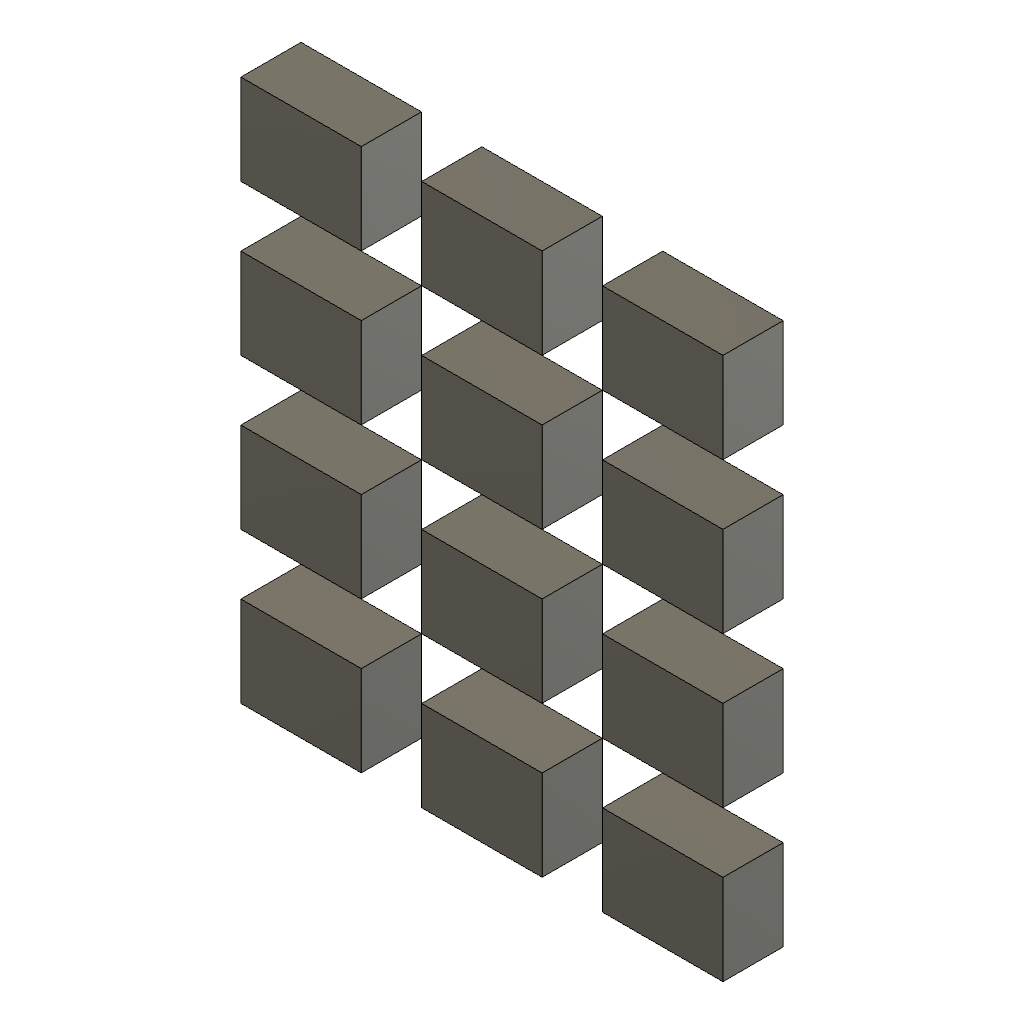
symmetric_one (Autodesk Fusion 360 design; units mm, degrees)
part number: 2026-10-20-19-21-12-779
Autodesk Fusion 360 part; units mm, degrees
sketch "Sketch1" plane through (0, 0, 0) normal (0, 0, 1) x (1, 0, 0)
  line L0 (10, 10) -> (50, 10)
  line L1 (50, 10) -> (50, 40)
  line L2 (50, 40) -> (10, 40)
  line L3 (10, 40) -> (10, 10)
extrude "Extrude1" add sketch "Sketch1" along normal blind 20 makes body 1
pattern_linear "ProbePattern" count 3 spacing 60 along (1, 0, 0) both ways count 4 spacing 50 along (0, 1, 0) of bodies 1 makes body 2 at (-36.6667, 30, 0) makes body 3 at (83.3333, 30, 0) makes body 4 at (-36.6667, 80, 0) makes body 5 at (23.3333, 80, 0) makes body 6 at (83.3333, 80, 0) makes body 7 at (-36.6667, 130, 0) makes body 8 at (23.3333, 130, 0) makes body 9 at (83.3333, 130, 0) makes body 10 at (-36.6667, 180, 0) makes body 11 at (23.3333, 180, 0) makes body 12 at (83.3333, 180, 0)
